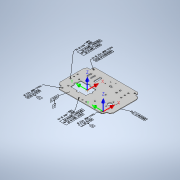
# Autodesk Inventor part: INV_nist_ftc_09_asme1_2020
Saved by Autodesk Inventor 2021 (Build 250183000, 183)
## iProperties
Created: 2016-11-30
Part Number: INV_nist_ftc_09_asme1_2020
Material: Generic
Document SubType Name: Sheet Metal
Designer: t_liuje
Density: 1 g/cm^3
Sheet Metal Rule: Default
Appearance: Default
Author: t_liuje
Autodesk Inventor part; units mm, degrees
ref_plane "YZ Plane" through (0, 0, 0) normal (1, 0, 0) x (0, 1, 0)
ref_plane "XZ Plane" through (0, 0, 0) normal (0, 1, 0) x (-1, 0, 0)
ref_plane "XY Plane" through (0, 0, 0) normal (0, 0, 1) x (1, 0, 0)
sketch "Sketch1" plane through (0, 0, 0) normal (0, 1, 0) x (-1, 0, 0)
  line L0 (139.7, -95.25) -> (-139.7, -95.25)
  line L1 (-139.7, -95.25) -> (-139.7, 95.25)
  line L2 (-139.7, 95.25) -> (139.7, 95.25)
  line L3 (139.7, 95.25) -> (139.7, -95.25)
  line L4 (182.8983, 0) -> (-210.5892, 0) construction
  line L5 (0, 76.0183) -> (0, -155.1524) construction
  line L6 (92.075, -57.15) -> (92.075, -38.1)
  line L7 (98.425, -38.1) -> (98.425, -57.15)
  arc A0 (92.075, -57.15) -> (98.425, -57.15) centre (95.25, -57.15) ccw
  arc A1 (98.425, -38.1) -> (92.075, -38.1) centre (95.25, -38.1) ccw
  line L8 (73.025, -57.15) -> (73.025, -38.1)
  line L9 (79.375, -38.1) -> (79.375, -57.15)
  arc A2 (73.025, -57.15) -> (79.375, -57.15) centre (76.2, -57.15) ccw
  arc A3 (79.375, -38.1) -> (73.025, -38.1) centre (76.2, -38.1) ccw
  circle A4 centre (101.6, 0) radius 3.175
  circle A5 centre (128.27, -19.05) radius 3.175
  circle A6 centre (128.27, 0) radius 3.175
  circle A7 centre (128.27, 19.05) radius 3.175
  circle A8 centre (101.6, 57.15) radius 3.175
  circle A9 centre (-38.1, 0) radius 3.175
  circle A10 centre (-38.1, 57.15) radius 3.175
  circle A11 centre (0, 83.82) radius 3.175
  circle A12 centre (19.05, 83.82) radius 3.175
  circle A13 centre (-19.05, 83.82) radius 3.175
  line L10 (84.7004, 28.6512) -> (19.05, 28.6512) construction
  line L11 (50.5968, 12.8479) -> (50.5968, 53.975) construction
  circle A14 centre (-91.44, 31.75) radius 9.525
  circle A15 centre (-91.44, 50.8) radius 2.8067
  circle A16 centre (-91.44, 12.7) radius 2.8067
  circle A17 centre (-110.49, 17.78) radius 1.9812
  circle A18 centre (-110.49, 7.62) radius 1.9812
  circle A19 centre (-110.49, 45.72) radius 1.9812
  circle A20 centre (-110.49, 55.88) radius 1.9812
  arc A21 (-17.1182, -52.578) -> (-17.1182, -49.022) centre (-12.7, -50.8) ccw
  arc A22 (-20.32, -49.022) -> (-20.32, -52.578) centre (-20.32, -50.8) ccw
  line L12 (-12.7, -50.8) -> (-20.32, -50.8) construction
  line L13 (-20.32, -52.578) -> (-17.1182, -52.578)
  line L14 (-20.32, -49.022) -> (-17.1182, -49.022)
  circle A23 centre (-57.15, -57.15) radius 4.0005
  circle A24 centre (-91.44, -66.04) radius 3.5687
  circle A25 centre (-57.15, -38.1) radius 4.0005
  circle A26 centre (-91.44, -46.99) radius 3.5687
  circle A27 centre (-91.44, -27.94) radius 3.5687
  circle A28 centre (7.0612, -70.5612) radius 1.9812
  circle A29 centre (-12.7, -78.74) radius 1.9812
  circle A30 centre (15.24, -50.8) radius 1.9812
  line L15 (46.0375, -61.8998) -> (46.0375, -33.3248)
  line L16 (55.5625, -33.3248) -> (55.5625, -61.8998)
  arc A31 (46.0375, -61.8998) -> (55.5625, -61.8998) centre (50.8, -61.8998) ccw
  arc A32 (55.5625, -33.3248) -> (46.0375, -33.3248) centre (50.8, -33.3248) ccw
  arc A33 (44.2468, 1.651) -> (56.9468, 1.651) centre (50.5968, 1.651) ccw
  arc A34 (9.6012, 35.0012) -> (9.6012, 22.3012) centre (9.6012, 28.6512) ccw
  arc A35 (91.5924, 22.3012) -> (91.5924, 35.0012) centre (91.5924, 28.6512) ccw
  arc A36 (56.9468, 55.6514) -> (44.2468, 55.6514) centre (50.5968, 55.6514) ccw
  line L17 (9.6012, 1.651) -> (44.2468, 1.651)
  line L18 (56.9468, 1.651) -> (91.5924, 1.651)
  line L19 (91.5924, 1.651) -> (91.5924, 22.3012)
  line L20 (91.5924, 35.0012) -> (91.5924, 55.6514)
  line L21 (9.6012, 55.6514) -> (9.6012, 35.0012)
  line L22 (9.6012, 22.3012) -> (9.6012, 1.651)
  line L23 (91.5924, 55.6514) -> (56.9468, 55.6514)
  line L24 (44.2468, 55.6514) -> (9.6012, 55.6514)
  point P0 (0, 0)
  dimension "d0" = 279.4
  dimension "d1" = 190.5
  dimension "d4" = 44.45
  dimension "d5" = 38.1
  dimension "d6" = 6.35
  dimension "d7" = 19.05
  dimension "d8" = 6.35
  dimension "d9" = 19.05
  dimension "d10" = 19.05
  dimension "d11" = 38.1
  dimension "d12" = 6.35
  dimension "d13" = 38.1
  dimension "d14" = 6.35
  dimension "d15" = 6.35
  dimension "d16" = 6.35
  dimension "d17" = 11.43
  dimension "d18" = 11.43
  dimension "d19" = 11.43
  dimension "d20" = 19.05
  dimension "d21" = 19.05
  dimension "d22" = 6.35
  dimension "d23" = 38.1
  dimension "d24" = 38.1
  dimension "d25" = 6.35
  dimension "d26" = 6.35
  dimension "d27" = 101.6
  dimension "d28" = 101.6
  dimension "d29" = 38.1
  dimension "d30" = 6.35
  dimension "d31" = 6.35
  dimension "d32" = 6.35
  dimension "d33" = 11.43
  dimension "d34" = 11.43
  dimension "d35" = 11.43
  dimension "d36" = 19.05
  dimension "d37" = 19.05
  dimension "d38" = 81.9912
  dimension "d39" = 54.0004
  dimension "d40" = 66.5988
  dimension "d41" = 89.1032
  dimension "d42" = 19.05
  dimension "d43" = 48.26
  dimension "d44" = 63.5
  dimension "d45" = 5.6134
  dimension "d46" = 48.26
  dimension "d47" = 19.05
  dimension "d48" = 19.05
  dimension "d49" = 48.26
  dimension "d50" = 3.9624
  dimension "d51" = 3.9624
  dimension "d52" = 3.9624
  dimension "d53" = 3.9624
  dimension "d54" = 29.21
  dimension "d55" = 29.21
  dimension "d56" = 29.21
  dimension "d57" = 29.21
  dimension "d58" = 10.16
  dimension "d59" = 13.97
  dimension "d60" = 13.97
  dimension "d61" = 10.16
  dimension "d63" = 1.778
  dimension "d64" = 7.62
  dimension "d65" = 3.556
  dimension "d66" = 127
  constraints: 50 end point, 37 centre point, 24 point on circle, 14 point on line, 13 parallel, 12 tangent, 7 horizontal, 6 vertical, 5 perpendicular, 4 collinear, 1 equal radius, 9 other
  measures "d0" distance of L1.end L2.end
  measures "d1" distance of L0.end L1.end
  measures "d4" distance from line of L3 A0.centre
  measures "d5" distance from line of L0 A0.centre
  measures "d6" distance between parallel lines of L7 L6
  measures "d7" distance of A1.centre A0.centre
  measures "d8" distance between parallel lines of L9 L8
  measures "d9" distance of A3.centre A2.centre
  measures "d10" distance of A0.centre A2.centre
  measures "d11" distance from line of A2.centre L0
  measures "d12" diameter of A4
  measures "d13" distance from line of L3 A4.centre
  measures "d14" diameter of A5
  measures "d15" diameter of A6
  measures "d16" diameter of A7
  measures "d17" distance from line of L3 A5.centre
  measures "d18" distance from line of L3 A6.centre
  measures "d19" distance from line of L3 A7.centre
  measures "d20" distance of A5.centre A6.centre
  measures "d21" distance of A7.centre A6.centre
  measures "d22" diameter of A8
  measures "d23" distance from line of L3 A8.centre
  measures "d24" distance from line of L2 A8.centre
  measures "d25" diameter of A9
  measures "d26" diameter of A10
  measures "d27" distance from line of L1 A9.centre
  measures "d28" distance from line of L1 A10.centre
  measures "d29" distance from line of L2 A10.centre
  measures "d30" diameter of A11
  measures "d31" diameter of A12
  measures "d32" diameter of A13
  measures "d33" distance from line of L2 A11.centre
  measures "d34" distance from line of L2 A12.centre
  measures "d35" distance from line of L2 A13.centre
  measures "d36" distance of A11.centre A13.centre
  measures "d37" distance of A12.centre A11.centre
  measures "d38" distance of L20.end L21.start
  measures "d39" distance of L18.end L20.end
  measures "d40" distance between parallel lines of L2 L10
  measures "d41" distance between parallel lines of L3 L11
  measures "d42" diameter of A14
  measures "d43" distance from line of L1 A14.centre
  measures "d44" distance from line of L2 A14.centre
  measures "d45" diameter of A15
  measures "d46" distance from line of L1 A15.centre
  measures "d47" distance of A15.centre A14.centre
  measures "d48" distance of A14.centre A16.centre
  measures "d49" distance from line of L1 A16.centre
  measures "d50" diameter of A17
  measures "d51" diameter of A18
  measures "d52" diameter of A19
  measures "d53" diameter of A20
  measures "d54" distance from line of L1 A18.centre
  measures "d55" distance from line of L1 A17.centre
  measures "d56" distance from line of L1 A19.centre
  measures "d57" distance from line of L1 A20.centre
  measures "d58" distance of A18.centre A17.centre
  measures "d59" vertical distance of A14.centre A17.centre
  measures "d60" vertical distance of A14.centre A19.centre
  measures "d61" distance of A20.centre A19.centre
  measures "d63" radius of A22
  measures "d64" distance of L12.start L12.end
  measures "d65" distance between parallel lines of L14 L13
  measures "d66" distance from line of L1 L12.start
extrude "Plate1" add sketch "Sketch1" along normal blind 3.048
fillet "Corner Round1" radius 3.175 4 edges at (-91.5924, 1.524, 1.651) (-91.5924, 1.524, 55.6514) (-9.6012, 1.524, 55.6514) (-9.6012, 1.524, 1.651)
sketch "Sketch6" plane through (0, 3.048, 0) normal (0, 1, 0) x (1, 0, 0)
  line L0 (-139.7, 95.25) -> (139.7, 95.25) projected
  line L1 (-139.7, -95.25) -> (-139.7, 95.25) projected
  point P0 (-107.95, 82.55)
  dimension "d110" = 12.7
  dimension "d111" = 31.75
  measures "d110" distance from line of L0 point (-107.95, 82.55)
  measures "d111" distance from line of L1 point (-107.95, 82.55)
hole "Hole1" at (-107.95, 3.048, -82.55) direction (0, -1, 0) diameter 5.9436 end through all
sketch "Sketch2" plane through (0, 3.048, 0) normal (0, 1, 0) x (1, 0, 0)
  line L0 (-139.7, 95.25) -> (-117.475, 95.25)
  line L1 (-117.475, 95.25) -> (-117.475, 80.9498)
  line L2 (-123.825, 74.5998) -> (-139.7, 74.5998)
  line L3 (-139.7, 74.5998) -> (-139.7, 95.25)
  arc A0 (-123.825, 74.5998) -> (-117.475, 80.9498) centre (-123.825, 80.9498) ccw
  point P0 (0, 0)
  point P1 (-117.475, 74.5998)
  dimension "d140" = 22.225
  dimension "d141" = 20.6502
  dimension "d142" = 6.35
  constraints: 8 end point, 2 parallel, 2 point on circle, 2 point on line, 2 tangent, 1 centre point, 1 horizontal, 1 perpendicular
  measures "d140" distance of point (-117.475, 74.6) L2.end
  measures "d141" distance of L0.end point (-117.475, 74.6)
  measures "d142" radius of A0
extrude "Extrusion1" cut sketch "Sketch2" against normal up to surface (3.048 mm away)
mirror "Mirror1" about plane through (0, 0, 0) normal (0, 0, 1) of "Hole1", "Extrusion1"
mirror "Mirror2" about plane through (0, 0, 0) normal (1, 0, 0) of "Hole1", "Extrusion1", "Mirror1"
chamfer "Chamfer1" distance 0.762 angle 45 4 edges at (-107.95, 3.048, -85.5218) (-107.95, 3.048, 85.5218) (107.95, 3.048, 85.5218) (107.95, 3.048, -85.5218)
chamfer "Corner Chamfer1" distance 6.35 angle 45 4 edges at (-117.475, 1.524, -95.25) (117.475, 1.524, -95.25) (117.475, 1.524, 95.25) (-117.475, 1.524, 95.25)
chamfer "Chamfer2" distance 12.7 distance2 7.3406 1 edges at (-139.7, 1.524, -74.5998) measured on face at (-139.7, 1.524, -74.0998)
chamfer "Chamfer3" distance 12.7 distance2 7.3406 1 edges at (-139.7, 1.524, 74.5998) measured on face at (-139.7, 1.524, 74.0998)
chamfer "Corner Chamfer3" distance 12.7 distance2 7.3406 1 edges at (139.7, 1.524, -74.5998) measured on face at (139.7, 1.524, -74.0998)
chamfer "Corner Chamfer4" distance 12.7 distance2 7.3406 1 edges at (139.7, 1.524, 74.5998) measured on face at (139.7, 1.524, 74.0998)
sketch "Sketch3" plane through (0, 3.048, 0) normal (0, 1, 0) x (1, 0, 0)
  arc A0 (-22.4998, 65.3802) -> (-1.8802, 85.9998) centre (12.7, 50.8) ccw
  line L0 (-21.886, 73.1817) -> (-21.886, 84.6893) construction
  line L1 (-21.886, 84.6893) -> (-8.0769, 84.6893) construction
  line L2 (-8.0769, 84.6893) -> (-8.0769, 73.1817) construction
  line L3 (-8.0769, 73.1817) -> (-21.886, 73.1817) construction
  dimension "d14" = 6.35
  constraints: 2 point on circle, 1 centre point, 1 coincident, 2 other
sketch "Sketch4" plane through (0, 3.048, 0) normal (0, 1, 0) x (1, 0, 0)
  line L0 (-18.4161, 50.8233) -> (-12.0661, 50.8233)
  line L1 (12.7, 82.1076) -> (12.7, 75.7576)
  line L2 (-4.8114, 68.3141) -> (-9.3042, 72.8016)
  arc A0 (-4.3259, 72.9612) -> (-9.5914, 67.655) centre (12.6842, 50.8158) ccw
  point P0 (-7.0612, 70.5612)
  dimension "d14" = 6.35
  constraints: 6 end point, 3 point on circle, 1 centre point, 1 horizontal, 1 point on line, 1 vertical
sketch "Sketch5" plane through (0, 3.048, 0) normal (0, 1, 0) x (1, 0, 0)
  line L0 (97.8824, 66.04) -> (85.1824, 66.04)
  line L1 (91.5324, 59.9356) -> (91.5324, 72.6356)
  point P0 (91.44, 66.04)
  constraints: 4 end point, 1 horizontal, 1 point on line, 1 vertical
equation "\"d17\" = d18"
equation "\"d19\" = d18"
equation "\"d21\" = d20"
equation "\"d34\" = d33"
equation "\"d35\" = d33"
equation "\"d48\" = d47"
equation "\"d55\" = d54"
equation "\"d56\" = d55"
equation "\"d57\" = d54"
equation "\"d60\" = d59"
equation "\"d61\" = d58"
equation "\"BendRadius\" = Thickness"
equation "\"BendReliefWidth\" = Thickness"
equation "\"BendReliefDepth\" = 0.5 * Thickness"
equation "\"CornerReliefSize\" = 4 * Thickness"
equation "\"MinimumRemnant\" = 2 * Thickness"
equation "\"JacobiRadiusSize\" = BendRadius"
equation "\"GapSize\" = Thickness"
equation "\"d105\" = BendRadius"
equation "\"Thickness\" = 3.048"
body "Solid1"
